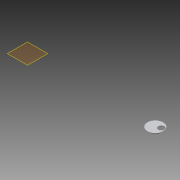
# Autodesk Inventor part: Lens_Cover
Saved by Autodesk Inventor 2013 (Build 170138000, 138)
## iProperties
Created: 2013-10-01
Part Number: Lens_Cover
Material: Generic
Document SubType Name: Modeling
Designer: Jeff
Density: 1 g/cm^3
Author: Jeff
Autodesk Inventor part; units mm, degrees
ref_plane "YZ Plane" through (0, 0, 0) normal (1, 0, 0) x (0, 1, 0)
ref_plane "XZ Plane" through (0, 0, 0) normal (0, 1, 0) x (-1, 0, 0)
ref_plane "XY Plane" through (0, 0, 0) normal (0, 0, 1) x (1, 0, 0)
ref_plane "Work Plane1" through (-323.1766, 0, 0) normal (0, 0, 1) x (1, 0, 0)
sketch "Sketch1" plane through (-323.1766, 0, 0) normal (0, 0, 1) x (1, 0, 0)
  circle A0 centre (490.0699, 1.9999) radius 31.1722 projected
  circle A1 centre (490.0699, 1.9999) radius 30.1722
  circle A2 centre (505.8508, 9.4466) radius 6.8 projected
  circle A3 centre (505.8508, 9.4466) radius 11.5
  line L0 (490.0699, 1.9999) -> (510.7388, 1.9999)
  dimension "d9" = 1
  dimension "d10" = 23
  constraints: 2 centre point, 2 end point
  measures "d9" radial gap between concentric circles of A0 A1
  measures "d10" diameter of A3
extrude "Extrusion4" add sketch "Sketch1" against normal blind 2 contours A1
ref_plane "Work Plane2" through (182.6743, 9.4467, 0) normal (-0.4268, 0.9044, 0) x (0, 0, -1)
body "Solid2"
